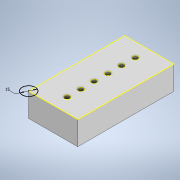
# Autodesk Inventor part: suport_butoane_comanda
Saved by Autodesk Inventor 2022.6 (Build 266554000, 554)
## iProperties
Created: 2025-09-19
Part Number: suport_butoane_comanda
Material: Generic
Document SubType Name: Modeling
Designer: Dragos Macovei
Density: 1 g/cm^3
Appearance: Default
Author: Dragos Macovei
Autodesk Inventor part; units mm, degrees
ref_plane "YZ Plane" through (0, 0, 0) normal (1, 0, 0) x (0, 1, 0)
ref_plane "XZ Plane" through (0, 0, 0) normal (0, 1, 0) x (-1, 0, 0)
ref_plane "XY Plane" through (0, 0, 0) normal (0, 0, 1) x (1, 0, 0)
sketch "Sketch1" plane through (0, 0, 0) normal (0, 1, 0) x (-1, 0, 0)
  line L0 (0, 0) -> (56, 0)
  line L1 (56, 0) -> (56, 109.3)
  line L2 (56, 109.3) -> (0, 109.3)
  line L3 (0, 109.3) -> (0, 0)
  line L4 (52, 105.3) -> (4, 105.3)
  line L5 (4, 105.3) -> (4, 4)
  line L6 (4, 4) -> (52, 4)
  line L7 (52, 4) -> (52, 105.3)
  dimension "d0" = 4
  dimension "d1" = 4
  dimension "d2" = 4
  dimension "d3" = 4
  dimension "d4" = 109.3
  dimension "d5" = 56
  constraints: 16 end point, 4 parallel, 2 horizontal, 2 perpendicular
  measures "d0" distance between parallel lines of L0 L6
  measures "d1" distance between parallel lines of L2 L4
  measures "d2" distance between parallel lines of L5 L3
  measures "d3" distance between parallel lines of L1 L7
  measures "d4" distance between parallel lines of L0 L2
  measures "d5" distance between parallel lines of L3 L1
extrude "Extrusion1" add sketch "Sketch1" along normal blind 27
sketch "Sketch2" plane through (0, 27, 0) normal (0, 1, 0) x (1, 0, 0)
  line L0 (-52, -105.3) -> (-52, -4) projected
  line L1 (-56, 0) -> (-56, -109.3) projected
  line L2 (-56, -109.3) -> (0, -109.3) projected
  line L3 (0, -109.3) -> (0, 0) projected
  line L4 (0, 0) -> (-56, 0) projected
  line L5 (-52, -105.3) -> (-52, -4) projected
  line L6 (-52, -4) -> (-4, -4) projected
  line L7 (-4, -4) -> (-4, -105.3) projected
  line L8 (-4, -105.3) -> (-52, -105.3) projected
  point P0 (-52, -4)
extrude "Extrusion2" add sketch "Sketch2" against normal blind 4 contours L0 L6 L7 L8
sketch "Sketch3" plane through (0, 27, 0) normal (0, 1, 0) x (1, 0, 0)
  line L0 (-56, 0) -> (-56, -109.3) projected
  line L1 (-56, -109.3) -> (0, -109.3) projected
  line L2 (0, -109.3) -> (0, 0) projected
  line L3 (0, 0) -> (-56, 0) projected
  line L4 (-56, -109.3) -> (0, -109.3) projected
  line L5 (-28, -109.3) -> (-28, 0)
  line L6 (0, 0) -> (-56, 0) projected
  circle A0 centre (-28, -15.9) radius 3.025
  circle A1 centre (-28, -31.4) radius 3.025
  circle A2 centre (-28, -77.8981) radius 3.025
  circle A3 centre (-28.2439, -62.4) radius 3.025
  circle A4 centre (-28, -93.3981) radius 3.025
  circle A5 centre (-28, -46.9) radius 3.025
  dimension "d11" = 6.05
  dimension "d13" = 6.05
  dimension "d14" = 6.05
  dimension "d15" = 6.05
  dimension "d16" = 6.05
  dimension "d17" = 6.05
  dimension "d18" = 109.3
  dimension "d19" = 15.5
  dimension "d20" = 15.5
  dimension "d21" = 15.5
  dimension "d22" = 15.5
  dimension "d23" = 15.5
  dimension "d25" = 15.9
  dimension "d26" = 15.9019
  constraints: 6 centre point, 5 point on line, 4 midpoint, 2 end point
  measures "d11" diameter of A0
  measures "d13" diameter of A1
  measures "d14" diameter of A2
  measures "d15" diameter of A3
  measures "d16" diameter of A4
  measures "d17" diameter of A5
  measures "d18" distance of L5.start L5.end
  measures "d19" distance of A3.centre A2.centre
  measures "d20" vertical distance of A5.centre A3.centre
  measures "d21" distance of A4.centre A2.centre
  measures "d22" distance of A5.centre A1.centre
  measures "d23" distance of A1.centre A0.centre
  measures "d25" distance of point (-28, 0) A0.centre
  measures "d26" distance of A4.centre point (-28, -109.3)
extrude "Extrusion3" cut sketch "Sketch3" against normal blind 4 contours A0 L5 | L5 A0 | A4 L5 | L5 A4 | A1 L5 | L5 A1 | A2 L5 | L5 A2 | A5 L5 | L5 A5 | A3 L5 | L5 A3
sketch "Sketch4" plane through (0, 27, 0) normal (0, 1, 0) x (1, 0, 0)
  circle A0 centre (-28.2439, -62.4) radius 3.025 projected
  circle A1 centre (-28, -15.9) radius 3.025 projected
  circle A2 centre (-28, -77.8981) radius 3.025 projected
  circle A3 centre (-28, -46.9) radius 3.025 projected
  circle A4 centre (-28, -31.4) radius 3.025 projected
  circle A5 centre (-28, -93.3981) radius 3.025 projected
  line L0 (-56, 0) -> (-56, -109.3) projected
  line L1 (-56, -109.3) -> (0, -109.3) projected
  line L2 (0, -109.3) -> (0, 0) projected
  line L3 (0, 0) -> (-56, 0) projected
  line L4 (-56, 0) -> (-56, -109.3) projected
  circle A6 centre (-56, -109.3) radius 7.5
  dimension "d29" = 15
  constraints: 1 centre point, 1 coincident
  measures "d29" diameter of A6
equation "\"d20\" = d19"
equation "\"d21\" = d19"
equation "\"d22\" = d20"
equation "\"d23\" = d19"
body "Solid1"
